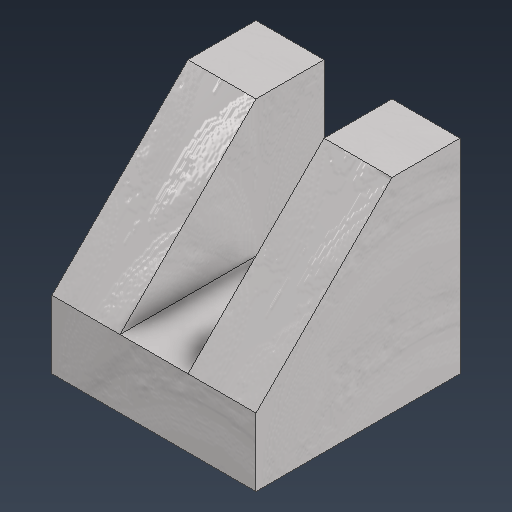
# Autodesk Inventor part: IsometricTwo
Saved by Autodesk Inventor 2026.4 (Build 304435000, 435)
## iProperties
Created: 2026-09-06
Part Number: IsometricTwo
Material: Generic
Document SubType Name: Modeling
Designer: YmCris
Density: 1 g/cm^3
Appearance: Default
Author: YmCris
Autodesk Inventor part; units mm, degrees
ref_plane "XZ Plane" through (0, 0, 0) normal (0, 1, 0) x (-1, 0, 0)
ref_plane "XY Plane" through (0, 0, 0) normal (0, 0, 1) x (1, 0, 0)
sketch "Sketch1" plane through (0, 0, 0) normal (0, 1, 0) x (-1, 0, 0)
  line L0 (-15, -15) -> (15, -15)
  line L1 (15, -15) -> (15, 15)
  line L2 (15, 15) -> (-15, 15)
  line L3 (-15, 15) -> (-15, -15)
  point P0 (0, 0)
  constraints: 8 end point, 2 parallel, 1 horizontal, 1 perpendicular
extrude "Extrusion1" add sketch "Sketch1" along normal blind 10
sketch "Sketch2" plane through (0, 10, 0) normal (0, 1, 0) x (1, 0, 0)
  line L0 (-15, 15) -> (-15, -15) projected
  line L1 (-15, 15) -> (-5, 15)
  line L2 (-5, 15) -> (-5, 5)
  line L3 (-5, 5) -> (-15, 5)
  line L4 (-15, 5) -> (-15, 15)
  line L5 (15, 15) -> (-15, 15) construction
  line L6 (0, 15) -> (0, 4.6859) construction
  line L7 (15, 15) -> (5, 15)
  line L8 (5, 15) -> (5, 5)
  line L9 (5, 5) -> (15, 5)
  line L10 (15, 5) -> (15, 15)
  point P0 (0, 0)
  constraints: 18 end point, 3 symmetric about line, 2 parallel, 1 horizontal, 1 midpoint, 1 perpendicular, 1 vertical
extrude "Extrusion2" add sketch "Sketch2" along normal blind 20
ref_plane "Work Plane1" through (-10, 0, 0) normal (1, 0, 0) x (0, 1, 0)
sketch "Sketch4" plane through (-10, 0, 0) normal (1, 0, 0) x (0, 1, 0)
  line L0 (0, 15) -> (10, 15) projected
  line L1 (10, -5) -> (30, -5) projected
  line L2 (10, 15) -> (30, -5)
  point P0 (0, 0)
  constraints: 2 end point
extrude "Rib1" add sketch "Sketch4" along normal mid plane 10 rib yes fills toward (5, 14.95) open curves L0 L2 L1
mirror "Mirror1" about plane through (0, 0, 0) normal (1, 0, 0) of "Rib1"
body "Solid1"
